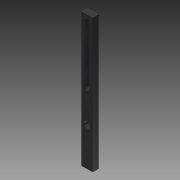
# Autodesk Inventor part: cyclic_base
Saved by Autodesk Inventor 2015 (Build 190159000, 159)
## iProperties
Created: 2022-11-07
Part Number: cyclic_base
Material: Generic
Document SubType Name: Modeling
Designer: Pavel Brodský
Density: 1 g/cm^3
Appearance: Default
Author: Pavel Brodský
Autodesk Inventor part; units mm, degrees
ref_plane "YZ Plane" through (0, 0, 0) normal (1, 0, 0) x (0, 1, 0)
ref_plane "XZ Plane" through (0, 0, 0) normal (0, 1, 0) x (-1, 0, 0)
ref_plane "XY Plane" through (0, 0, 0) normal (0, 0, 1) x (1, 0, 0)
sketch "Náčrt1" plane through (0, 0, 0) normal (0, 0, 1) x (1, 0, 0)
  line L0 (0, 0) -> (15, 0)
  line L1 (15, 0) -> (15, 8)
  line L2 (15, 8) -> (0, 8)
  line L3 (0, 8) -> (0, 0)
  dimension "d0" = 15
  dimension "d1" = 8
  constraints: 8 end point, 2 parallel, 1 horizontal, 1 perpendicular
  measures "d0" distance of L1.end L2.end
  measures "d1" distance between parallel lines of L0 L2
extrude "Vysunutí1" add sketch "Náčrt1" along normal blind 175
sketch "Náčrt2" plane through (0, 8, 0) normal (0, 1, 0) x (1, 0, 0)
  circle A0 centre (7.5, -50) radius 4
  line L0 (15, 0) -> (0, 0) projected
  line L1 (15, 0) -> (15, -175) projected
  arc A1 (5, -168) -> (10, -168) centre (7.5, -168) ccw
  arc A2 (10, -91) -> (5, -91) centre (7.5, -91) ccw
  line L2 (5, -168) -> (5, -91)
  line L3 (10, -168) -> (10, -91)
  line L4 (15, -175) -> (0, -175) projected
  dimension "d4" = 8
  dimension "d5" = 50
  dimension "d6" = 7.5
  dimension "d7" = 5
  dimension "d8" = 5
  dimension "d9" = 7.5
  dimension "d10" = 77
  dimension "d11" = 7
  constraints: 4 end point, 4 point on circle, 4 tangent, 3 centre point, 1 vertical alignment
  measures "d4" diameter of A0
  measures "d5" distance from line of L0 A0.centre
  measures "d6" distance from line of L1 A0.centre
  measures "d7" diameter of A1
  measures "d8" diameter of A2
  measures "d9" horizontal distance of A1.centre L1.end
  measures "d10" distance of A2.centre A1.centre
  measures "d11" distance from line of L4 A1.centre
extrude "Vysunutí2" cut sketch "Náčrt2" against normal blind 175
equation "\"d8\" = d7"
